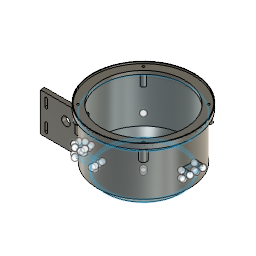
porsche-911-f-model-dash-subwoofer (Autodesk Fusion 360 design; units mm, degrees)
part number: 2026-11-07-18-42-40-753
Autodesk Fusion 360 part; units mm, degrees
sketch "Sketch1" plane through (0, 0, 0) normal (0, 0, 1) x (1, 0, 0)
  circle A0 centre (0, 0) radius 44
  dimension "d40" = 88
  measures "d40" diameter of A0
ref_plane "WorkPlane1" through (0, 0, 10) normal (0, 0, 1) x (1, 0, 0)
sketch "Sketch2" plane through (0, 0, 10) normal (0, 0, 1) x (1, 0, 0)
  circle A0 centre (0, 0) radius 54
  dimension "d43" = 108
  measures "d43" diameter of A0
loft "RearCone" add profiles "Sketch1", "Sketch2" section 1 section 2 makes body 1
extrude "StraightBody" add sketch "Sketch2" along normal blind 49 bodies 1
ref_plane "WorkPlane2" through (0, 0, 59) normal (0, 0, 1) x (1, 0, 0)
sketch "Sketch3" plane through (0, 0, 59) normal (0, 0, 1) x (1, 0, 0)
  circle A0 centre (0, 0) radius 54
  dimension "d48" = 108
  measures "d48" diameter of A0
ref_plane "WorkPlane3" through (0, 0, 64) normal (0, 0, 1) x (1, 0, 0)
sketch "Sketch4" plane through (0, 0, 64) normal (0, 0, 1) x (1, 0, 0)
  circle A0 centre (0, 0) radius 59
  dimension "d51" = 118
  measures "d51" diameter of A0
loft "FrontFlare" add profiles "Sketch3", "Sketch4" section 1 section 2 bodies 1
extrude "FrontRing" add sketch "Sketch4" along normal blind 6 bodies 1
ref_plane "WorkPlane4" through (0, 0, 3) normal (0, 0, 1) x (1, 0, 0)
sketch "Sketch5" plane through (0, 0, 3) normal (0, 0, 1) x (1, 0, 0)
  circle A0 centre (0, 0) radius 44
  dimension "d56" = 88
  measures "d56" diameter of A0
sketch "Sketch6" plane through (0, 0, 10) normal (0, 0, 1) x (1, 0, 0)
  circle A0 centre (0, 0) radius 51
  dimension "d57" = 102
  measures "d57" diameter of A0
loft "InnerRearCone" cut profiles "Sketch5", "Sketch6" section 1 section 2 bodies 1
extrude "MainChamber" cut sketch "Sketch6" along normal blind 54 bodies 1
sketch "Sketch7" plane through (0, 0, 64) normal (0, 0, 1) x (1, 0, 0)
  circle A0 centre (0, 0) radius 48.5
  dimension "d60" = 97
  measures "d60" diameter of A0
extrude "SpeakerCutout" cut sketch "Sketch7" along normal blind 6 bodies 1
ref_plane "WorkPlane5" through (0, 0, 68) normal (0, 0, 1) x (1, 0, 0)
sketch "Sketch8" plane through (0, 0, 68) normal (0, 0, 1) x (1, 0, 0)
  circle A0 centre (0, 0) radius 58.25
  circle A1 centre (0, 0) radius 48.5
  dimension "d65" = 116.5
  dimension "d66" = 97
  measures "d65" diameter of A0
  measures "d66" diameter of A1
extrude "SpeakerSeat" cut sketch "Sketch8" along normal blind 2 bodies 1
ref_plane "WorkPlane6" through (0, 0, 50) normal (0, 0, 1) x (1, 0, 0)
sketch "Sketch9" plane through (0, 0, 50) normal (0, 0, 1) x (1, 0, 0)
  circle A0 centre (38.1838, 38.1838) radius 4
  circle A1 centre (-38.1838, 38.1838) radius 4
  circle A2 centre (-38.1838, -38.1838) radius 4
  circle A3 centre (38.1838, -38.1838) radius 4
  dimension "d71" = 8
  dimension "d72" = 8
  dimension "d73" = 8
  dimension "d74" = 8
  measures "d71" diameter of A0
  measures "d72" diameter of A1
  measures "d73" diameter of A2
  measures "d74" diameter of A3
extrude "4x_Speaker_Bosses" add sketch "Sketch9" along normal blind 18 bodies 1
sketch "Sketch10" plane through (0, 0, 50) normal (0, 0, 1) x (1, 0, 0)
  circle A0 centre (38.1838, 38.1838) radius 1.3
  circle A1 centre (-38.1838, 38.1838) radius 1.3
  circle A2 centre (-38.1838, -38.1838) radius 1.3
  circle A3 centre (38.1838, -38.1838) radius 1.3
  dimension "d77" = 2.6
  dimension "d78" = 2.6
  dimension "d79" = 2.6
  dimension "d80" = 2.6
  measures "d77" diameter of A0
  measures "d78" diameter of A1
  measures "d79" diameter of A2
  measures "d80" diameter of A3
extrude "4x_Speaker_Boss_Pilot_Holes" cut sketch "Sketch10" along normal blind 18 bodies 1
sketch "MountPlate_SHIFTED_25mm" plane through (0, 0, 0) normal (0, 0, 1) x (1, 0, 0)
  line L0 (-98, -22.5) -> (-58, -22.5)
  line L1 (-58, -22.5) -> (-58, -17.5)
  line L2 (-58, -17.5) -> (-98, -17.5)
  line L3 (-98, -17.5) -> (-98, -22.5)
extrude "MountPlate_40x45x5_SHIFTED" add sketch "MountPlate_SHIFTED_25mm" along normal blind 45 separate body makes body 2
sketch "Sketch12" plane through (0, 0, 0) normal (0, 0, 1) x (1, 0, 0)
  line L0 (-58, -22.5) -> (-34, -22.5)
  line L1 (-34, -22.5) -> (-34, -17.5)
  line L2 (-34, -17.5) -> (-58, -17.5)
  line L3 (-58, -17.5) -> (-58, -22.5)
sketch "Sketch13" plane through (0, 0, 10) normal (0, 0, 1) x (1, 0, 0)
  line L0 (-58, -22.5) -> (-46, -22.5)
  line L1 (-46, -22.5) -> (-46, -17.5)
  line L2 (-46, -17.5) -> (-58, -17.5)
  line L3 (-58, -17.5) -> (-58, -22.5)
loft "Printable_Lower_Web_SHIFTED" add profiles "Sketch12", "Sketch13" section 1 section 2 separate body makes body 3
sketch "Sketch14" plane through (0, 0, 10) normal (0, 0, 1) x (1, 0, 0)
  line L0 (-58, -22.5) -> (-46, -22.5)
  line L1 (-46, -22.5) -> (-46, -17.5)
  line L2 (-46, -17.5) -> (-58, -17.5)
  line L3 (-58, -17.5) -> (-58, -22.5)
extrude "Continuous_Web_SHIFTED" add sketch "Sketch14" along normal blind 35 separate body makes body 4
sketch "Sketch15" plane through (0, 0, 0) normal (0, 0, 1) x (1, 0, 0)
  line L0 (-54, -26) -> (-34, -26)
  line L1 (-34, -26) -> (-34, -14)
  line L2 (-34, -14) -> (-54, -14)
  line L3 (-54, -14) -> (-54, -26)
sketch "Sketch16" plane through (0, 0, 10) normal (0, 0, 1) x (1, 0, 0)
  line L0 (-54, -26) -> (-47, -26)
  line L1 (-47, -26) -> (-47, -14)
  line L2 (-47, -14) -> (-54, -14)
  line L3 (-54, -14) -> (-54, -26)
loft "Lower_Reinforcement_SHORTER" add profiles "Sketch15", "Sketch16" section 1 section 2 separate body makes body 5
ref_plane "WorkPlane7" through (0, 0, 24) normal (0, 0, 1) x (1, 0, 0)
sketch "Sketch17" plane through (0, 0, 24) normal (0, 0, 1) x (1, 0, 0)
  line L0 (-54, -26) -> (-47, -26)
  line L1 (-47, -26) -> (-47, -14)
  line L2 (-47, -14) -> (-54, -14)
  line L3 (-54, -14) -> (-54, -26)
extrude "Upper_Reinforcement_SHORTER" add sketch "Sketch17" along normal blind 10 separate body makes body 6
sketch "LowerBlock_RearConnection_V251_Z0" plane through (0, 0, 0) normal (0, 0, 1) x (1, 0, 0)
  line L0 (-34.1, -26) -> (-30.9, -26)
  line L1 (-30.9, -26) -> (-33.8, -22.8)
  line L2 (-33.8, -22.8) -> (-34.1, -22.8)
  line L3 (-34.1, -22.8) -> (-34.1, -26)
sketch "LowerBlock_RearConnection_V251_Z10" plane through (0, 0, 10) normal (0, 0, 1) x (1, 0, 0)
  line L0 (-47.1, -26) -> (-43.9, -26)
  line L1 (-43.9, -26) -> (-46.8, -21.5)
  line L2 (-46.8, -21.5) -> (-47.1, -21.5)
  line L3 (-47.1, -21.5) -> (-47.1, -26)
loft "LowerBlock_RearConnection_V251_to_Cup" add profiles "LowerBlock_RearConnection_V251_Z0", "LowerBlock_RearConnection_V251_Z10" section 1 section 2 separate body makes body 7
sketch "UpperBlock_RearConnection_V251_Profile" plane through (0, 0, 24) normal (0, 0, 1) x (1, 0, 0)
  line L0 (-47.1, -26) -> (-43.9, -26)
  line L1 (-43.9, -26) -> (-46.8, -21.5)
  line L2 (-46.8, -21.5) -> (-47.1, -21.5)
  line L3 (-47.1, -21.5) -> (-47.1, -26)
extrude "UpperBlock_RearConnection_V251_to_Cup" add sketch "UpperBlock_RearConnection_V251_Profile" along normal blind 10 separate body makes body 8
combine "Join_V251_Mount_to_Cup" operation add target body 1 tool bodies 2 3 4 5 6 7 8
ref_plane "WorkPlane8" through (0, -25, 0) normal (0, 1, 0) x (0, 0, 1)
sketch "2x_Tyrap_Slot_3x12mm" plane through (0, -25, 0) normal (0, 1, 0) x (1, 0, 0)
  line L0 (-89.5, -5.5, 5) -> (-89.5, -14.5, 5)
  arc A0 through (-92.5, -14.5, 5) (-91, -16, 5) (-89.5, -14.5, 5)
  line L1 (-92.5, -14.5, 5) -> (-92.5, -5.5, 5)
  arc A1 through (-89.5, -5.5, 5) (-91, -4, 5) (-92.5, -5.5, 5)
  line L2 (-89.5, -30.5, 5) -> (-89.5, -39.5, 5)
  arc A2 through (-92.5, -39.5, 5) (-91, -41, 5) (-89.5, -39.5, 5)
  line L3 (-92.5, -39.5, 5) -> (-92.5, -30.5, 5)
  arc A3 through (-89.5, -30.5, 5) (-91, -29, 5) (-92.5, -30.5, 5)
extrude "2x_Tyrap_Slot_3x12mm_Cut" cut sketch "2x_Tyrap_Slot_3x12mm" along normal mid plane 10 contours L0 A0 L1 A1 | L2 A2 L3 A3 in plane through (0, -20, 0) normal (0, 1, 0) bodies 1
ref_plane "WorkPlane9" through (0, -25, 0) normal (0, 1, 0) x (0, 0, 1)
sketch "Porsche_SINGLE_10mm_BoltHole" plane through (0, -25, 0) normal (0, 1, 0) x (1, 0, 0)
  circle A0 through (-63, -28, 5) (-70.5, -23.6699, 5) (-70.5, -32.3301, 5)
  dimension "d99" = 10
extrude "Porsche_SINGLE_10mm_BoltHole_Cut" cut sketch "Porsche_SINGLE_10mm_BoltHole" along normal mid plane 10 contours A0 in plane through (0, -20, 0) normal (0, 1, 0) bodies 1
sketch "Sketch23" plane through (0, 0, 0) normal (0, 0, 1) x (1, 0, 0)
  circle A0 centre (23, 10) radius 5
  dimension "d102" = 10
  measures "d102" diameter of A0
extrude "Cable_Hole_Opposite_SHIFTED_Mount" cut sketch "Sketch23" along normal blind 6 bodies 1
ref_plane "WorkPlane10" through (0, 0, 23) normal (0, 0, 1) x (1, 0, 0)
sketch "ExtraSupport_RampBottom_Profile" plane through (0, 0, 23) normal (0, 0, 1) x (1, 0, 0)
  line L0 (52, -7.5) -> (54, -7.5)
  line L1 (54, -7.5) -> (54, 7.5)
  line L2 (54, 7.5) -> (52, 7.5)
  line L3 (52, 7.5) -> (52, -7.5)
ref_plane "WorkPlane11" through (0, 0, 31) normal (0, 0, 1) x (1, 0, 0)
sketch "ExtraSupport_RampTop_Profile" plane through (0, 0, 31) normal (0, 0, 1) x (1, 0, 0)
  line L0 (52, -7.5) -> (62, -7.5)
  line L1 (62, -7.5) -> (62, 7.5)
  line L2 (62, 7.5) -> (52, 7.5)
  line L3 (52, 7.5) -> (52, -7.5)
loft "ExtraSupport_45deg_Ramp" add profiles "ExtraSupport_RampBottom_Profile", "ExtraSupport_RampTop_Profile" section 1 section 2 bodies 1
sketch "ExtraSupport_FlatBlock" plane through (0, 0, 31) normal (0, 0, 1) x (1, 0, 0)
  line L0 (52, -7.5) -> (62, -7.5)
  line L1 (62, -7.5) -> (62, 7.5)
  line L2 (62, 7.5) -> (52, 7.5)
  line L3 (52, 7.5) -> (52, -7.5)
extrude "ExtraSupport_15x4x8" add sketch "ExtraSupport_FlatBlock" along normal blind 4 bodies 1
equation "SC_bodyDia = 108 mm" comment "Main cup body diameter."
equation "SC_totalDepth = 70 mm" comment "Overall cup depth."
equation "SC_wall = 3 mm" comment "Side wall."
equation "SC_rearWall = 3 mm" comment "Rear wall."
equation "SC_rearBaseDia = 88 mm" comment "Flat print foot."
equation "SC_rearConeHeight = 10 mm" comment "Rear cone height."
equation "SC_frontLipDia = 118 mm" comment "Short front lip."
equation "SC_frontFlareHeight = 5 mm" comment "Front flare."
equation "SC_frontRingThk = 6 mm" comment "Front ring."
equation "SC_cutoutDia = 97 mm" comment "Speaker cutout."
equation "SC_speakerSeatDia = 116.5 mm" comment "Speaker seat diameter."
equation "SC_speakerSeatDepth = 2 mm" comment "Speaker seat depth."
equation "SC_innerBodyDia = SC_bodyDia - 2 * SC_wall" comment "Inside body diameter."
equation "SC_innerRearDia = SC_rearBaseDia" comment "Inner rear start."
equation "SC_straightBodyHeight = SC_totalDepth - SC_rearConeHeight - SC_frontFlareHeight - SC_frontRingThk" comment "Straight body height."
equation "SC_mountPlateWidth = 40 mm" comment "Main mounting plate length."
equation "SC_mountPlateHeight = 45 mm" comment "Plate height from print bed."
equation "SC_mountPlateThk = 5 mm" comment "Plate/web thickness."
equation "SC_nominalGap = 10 mm" comment "Nominal horizontal clearance to body."
equation "SC_mountRearShift = 25 mm" comment "Whole mount shifted tangentially/rearward over body diameter."
equation "SC_porscheHoleDia = 10 mm" comment "Porsche holes."
equation "SC_porscheHoleSpacing = 24 mm" comment "Porsche hole spacing."
equation "SC_mountUpperHoleZ = 28 mm" comment "Single bolt-hole center height from closed underside after 10 mm downward correction."
equation "SC_reinforcementWidth = 12 mm" comment "Local reinforcement width."
equation "SC_reinforcementHeight = 10 mm" comment "Local reinforcement height."
equation "SC_reinforcementTrim = 3 mm" comment "Shortening of the two reinforcement blocks on the cup side."
equation "SC_reinforcementPlateTrim = 6 mm" comment "Shortening of both reinforcement blocks on the mounting-plate side."
equation "SC_cableHoleDia = 10 mm" comment "Cable pass-through."
equation "SC_speakerScrewDia = 3 mm" comment "Physical screw diameter."
equation "SC_speakerScrewLength = 20 mm" comment "Physical screw length."
equation "SC_bossOuterDia = 8 mm" comment "Boss outside diameter."
equation "SC_bossLength = 18 mm" comment "Boss length."
equation "SC_bossPilotDia = 2.6 mm" comment "Pilot hole for 3 mm screw."
equation "SC_bossPCD = 108 mm" comment "Boss pitch circle diameter."
equation "SC_supportWidth = 15 mm" comment "Tangential width of extra resting support."
equation "SC_supportBlockHeight = 4 mm" comment "Height of flat resting block."
equation "SC_supportDepth = 8 mm" comment "Visible radial projection outside cup wall."
equation "SC_supportTopFromTop = 35 mm" comment "Distance from cup top to top of support."
equation "SC_supportRampHeight = 8 mm" comment "45 degree build-up height under support."
equation "d40 = SC_rearBaseDia"
equation "d41 = SC_rearConeHeight"
equation "d43 = SC_bodyDia"
equation "d44 = SC_straightBodyHeight"
equation "d46 = SC_rearConeHeight + SC_straightBodyHeight"
equation "d48 = SC_bodyDia"
equation "d49 = SC_totalDepth - SC_frontRingThk"
equation "d51 = SC_frontLipDia"
equation "d52 = SC_frontRingThk"
equation "d54 = SC_rearWall"
equation "d56 = SC_innerRearDia"
equation "d57 = SC_innerBodyDia"
equation "d58 = SC_totalDepth - SC_frontRingThk - SC_rearConeHeight"
equation "d60 = SC_cutoutDia"
equation "d61 = SC_frontRingThk"
equation "d63 = SC_totalDepth - SC_speakerSeatDepth"
equation "d65 = SC_speakerSeatDia"
equation "d66 = SC_cutoutDia"
equation "d67 = SC_speakerSeatDepth"
equation "d69 = SC_totalDepth - SC_speakerSeatDepth - SC_bossLength"
equation "d71 = SC_bossOuterDia"
equation "d72 = SC_bossOuterDia"
equation "d73 = SC_bossOuterDia"
equation "d74 = SC_bossOuterDia"
equation "d75 = SC_bossLength"
equation "d77 = SC_bossPilotDia"
equation "d78 = SC_bossPilotDia"
equation "d79 = SC_bossPilotDia"
equation "d80 = SC_bossPilotDia"
equation "d81 = SC_bossLength"
equation "d83 = SC_mountPlateHeight"
equation "d99 = SC_porscheHoleDia"
equation "d102 = SC_cableHoleDia"
equation "d109 = SC_supportBlockHeight"
named bodies: "SubCup_v251"
